Autodesk Fusion 360 part; units mm, degrees
(part 8 of 28)
sketch "Blinking Light House-F_Cu" plane through (0, 0, 1.4859) normal (0, 0, 1) x (1, 0, 0)
  line L0 (23.2295, 32.6644) -> (23.3427, 32.6091)
  line L1 (23.3427, 32.6091) -> (23.4319, 32.5199)
  line L2 (23.4319, 32.5199) -> (23.4872, 32.4067)
  line L3 (23.4872, 32.4067) -> (23.5031, 32.2975)
  line L4 (23.5031, 32.2975) -> (23.5031, 30.6131)
  line L5 (23.5031, 30.6131) -> (23.4872, 30.5039)
  line L6 (23.4872, 30.5039) -> (23.4319, 30.3907)
  line L7 (23.4319, 30.3907) -> (23.3427, 30.3016)
  line L8 (23.3427, 30.3016) -> (23.2295, 30.2462)
  line L9 (23.2295, 30.2462) -> (23.1203, 30.2303)
  line L10 (23.1203, 30.2303) -> (20.9864, 30.2303)
  line L11 (20.9864, 30.2303) -> (19.0583, 28.3022)
  line L12 (19.0583, 28.3022) -> (19.0583, 14.5419)
  line L13 (19.0583, 14.5419) -> (24.7601, 8.8401)
  line L14 (24.7601, 8.8401) -> (30.8402, 8.8401)
  line L15 (30.8402, 8.8401) -> (33.2244, 11.2242)
  line L16 (33.2244, 11.2242) -> (33.2244, 13.5949)
  line L17 (33.2244, 13.5949) -> (33.2295, 13.6733)
  line L18 (33.2295, 13.6733) -> (33.27, 13.8245)
  line L19 (33.27, 13.8245) -> (33.3483, 13.9602)
  line L20 (33.3483, 13.9602) -> (33.4001, 14.0192)
  line L21 (33.4001, 14.0192) -> (35.4955, 16.1146)
  line L22 (35.4955, 16.1146) -> (35.5545, 16.1663)
  line L23 (35.5545, 16.1663) -> (35.6901, 16.2446)
  line L24 (35.6901, 16.2446) -> (35.8414, 16.2852)
  line L25 (35.8414, 16.2852) -> (35.9197, 16.2903)
  line L26 (35.9197, 16.2903) -> (37.4913, 16.2903)
  line L27 (37.4913, 16.2903) -> (37.5696, 16.2852)
  line L28 (37.5696, 16.2852) -> (37.7209, 16.2446)
  line L29 (37.7209, 16.2446) -> (37.723, 16.2434)
  line L30 (37.723, 16.2434) -> (41.6943, 16.2434)
  line L31 (41.6943, 16.2434) -> (41.7173, 16.2778)
  line L32 (41.7173, 16.2778) -> (41.8559, 16.4164)
  line L33 (41.8559, 16.4164) -> (42.0189, 16.5253)
  line L34 (42.0189, 16.5253) -> (42.2, 16.6003)
  line L35 (42.2, 16.6003) -> (42.3923, 16.6386)
  line L36 (42.3923, 16.6386) -> (42.4903, 16.6434)
  line L37 (42.4903, 16.6434) -> (43.6903, 16.6434)
  line L38 (43.6903, 16.6434) -> (43.7883, 16.6386)
  line L39 (43.7883, 16.6386) -> (43.9806, 16.6003)
  line L40 (43.9806, 16.6003) -> (44.1617, 16.5253)
  line L41 (44.1617, 16.5253) -> (44.3247, 16.4164)
  line L42 (44.3247, 16.4164) -> (44.4633, 16.2778)
  line L43 (44.4633, 16.2778) -> (44.5722, 16.1148)
  line L44 (44.5722, 16.1148) -> (44.6472, 15.9337)
  line L45 (44.6472, 15.9337) -> (44.6855, 15.7414)
  line L46 (44.6855, 15.7414) -> (44.6855, 15.5454)
  line L47 (44.6855, 15.5454) -> (44.6472, 15.3531)
  line L48 (44.6472, 15.3531) -> (44.5722, 15.172)
  line L49 (44.5722, 15.172) -> (44.5073, 15.0749)
  line L50 (44.5073, 15.0749) -> (47.4649, 12.1173)
  line L51 (47.4649, 12.1173) -> (51.3447, 12.1173)
  line L52 (51.3447, 12.1173) -> (51.3717, 12.1704)
  line L53 (51.3717, 12.1704) -> (51.487, 12.3291)
  line L54 (51.487, 12.3291) -> (51.6257, 12.4678)
  line L55 (51.6257, 12.4678) -> (51.7844, 12.5831)
  line L56 (51.7844, 12.5831) -> (51.9592, 12.6722)
  line L57 (51.9592, 12.6722) -> (52.1457, 12.7328)
  line L58 (52.1457, 12.7328) -> (52.3395, 12.7635)
  line L59 (52.3395, 12.7635) -> (52.4375, 12.7673)
  line L60 (52.4375, 12.7673) -> (52.9375, 12.7673)
  line L61 (52.9375, 12.7673) -> (53.0356, 12.7635)
  line L62 (53.0356, 12.7635) -> (53.2293, 12.7328)
  line L63 (53.2293, 12.7328) -> (53.4159, 12.6722)
  line L64 (53.4159, 12.6722) -> (53.5907, 12.5831)
  line L65 (53.5907, 12.5831) -> (53.7493, 12.4678)
  line L66 (53.7493, 12.4678) -> (53.888, 12.3291)
  line L67 (53.888, 12.3291) -> (54.0033, 12.1704)
  line L68 (54.0033, 12.1704) -> (54.0924, 11.9957)
  line L69 (54.0924, 11.9957) -> (54.153, 11.8091)
  line L70 (54.153, 11.8091) -> (54.1837, 11.6154)
  line L71 (54.1837, 11.6154) -> (54.1837, 11.4192)
  line L72 (54.1837, 11.4192) -> (54.153, 11.2255)
  line L73 (54.153, 11.2255) -> (54.0924, 11.039)
  line L74 (54.0924, 11.039) -> (54.0033, 10.8642)
  line L75 (54.0033, 10.8642) -> (53.888, 10.7055)
  line L76 (53.888, 10.7055) -> (53.7493, 10.5668)
  line L77 (53.7493, 10.5668) -> (53.5907, 10.4515)
  line L78 (53.5907, 10.4515) -> (53.4159, 10.3625)
  line L79 (53.4159, 10.3625) -> (53.2293, 10.3018)
  line L80 (53.2293, 10.3018) -> (53.0356, 10.2712)
  line L81 (53.0356, 10.2712) -> (52.9375, 10.2673)
  line L82 (52.9375, 10.2673) -> (52.4375, 10.2673)
  line L83 (52.4375, 10.2673) -> (52.3395, 10.2712)
  line L84 (52.3395, 10.2712) -> (52.1457, 10.3018)
  line L85 (52.1457, 10.3018) -> (51.9592, 10.3625)
  line L86 (51.9592, 10.3625) -> (51.7844, 10.4515)
  line L87 (51.7844, 10.4515) -> (51.6257, 10.5668)
  line L88 (51.6257, 10.5668) -> (51.487, 10.7055)
  line L89 (51.487, 10.7055) -> (51.3717, 10.8642)
  line L90 (51.3717, 10.8642) -> (51.3447, 10.9173)
  line L91 (51.3447, 10.9173) -> (47.2164, 10.9173)
  line L92 (47.2164, 10.9173) -> (47.1381, 10.9224)
  line L93 (47.1381, 10.9224) -> (46.9868, 10.963)
  line L94 (46.9868, 10.963) -> (46.8552, 11.039)
  line L95 (46.8552, 11.039) -> (46.8511, 11.0413)
  line L96 (46.8511, 11.0413) -> (46.7921, 11.093)
  line L97 (46.7921, 11.093) -> (43.2418, 14.6434)
  line L98 (43.2418, 14.6434) -> (42.4903, 14.6434)
  line L99 (42.4903, 14.6434) -> (42.3923, 14.6482)
  line L100 (42.3923, 14.6482) -> (42.2, 14.6865)
  line L101 (42.2, 14.6865) -> (42.0189, 14.7615)
  line L102 (42.0189, 14.7615) -> (41.8559, 14.8704)
  line L103 (41.8559, 14.8704) -> (41.7173, 15.009)
  line L104 (41.7173, 15.009) -> (41.6943, 15.0434)
  line L105 (41.6943, 15.0434) -> (37.5382, 15.0434)
  line L106 (37.5382, 15.0434) -> (37.4598, 15.0485)
  line L107 (37.4598, 15.0485) -> (37.3086, 15.0891)
  line L108 (37.3086, 15.0891) -> (37.3064, 15.0903)
  line L109 (37.3064, 15.0903) -> (36.1683, 15.0903)
  line L110 (36.1683, 15.0903) -> (34.4244, 13.3464)
  line L111 (34.4244, 13.3464) -> (34.4244, 10.9757)
  line L112 (34.4244, 10.9757) -> (34.4192, 10.8974)
  line L113 (34.4192, 10.8974) -> (34.3787, 10.7461)
  line L114 (34.3787, 10.7461) -> (34.3004, 10.6105)
  line L115 (34.3004, 10.6105) -> (34.2486, 10.5515)
  line L116 (34.2486, 10.5515) -> (31.513, 7.8158)
  line L117 (31.513, 7.8158) -> (31.454, 7.7641)
  line L118 (31.454, 7.7641) -> (31.3183, 7.6858)
  line L119 (31.3183, 7.6858) -> (31.1671, 7.6452)
  line L120 (31.1671, 7.6452) -> (31.0887, 7.6401)
  line L121 (31.0887, 7.6401) -> (24.5116, 7.6401)
  line L122 (24.5116, 7.6401) -> (24.4333, 7.6452)
  line L123 (24.4333, 7.6452) -> (24.282, 7.6858)
  line L124 (24.282, 7.6858) -> (24.1463, 7.7641)
  line L125 (24.1463, 7.7641) -> (24.0873, 7.8158)
  line L126 (24.0873, 7.8158) -> (18.034, 13.8691)
  line L127 (18.034, 13.8691) -> (17.9823, 13.9281)
  line L128 (17.9823, 13.9281) -> (17.904, 14.0638)
  line L129 (17.904, 14.0638) -> (17.8634, 14.2151)
  line L130 (17.8634, 14.2151) -> (17.8583, 14.2934)
  line L131 (17.8583, 14.2934) -> (17.8583, 28.5507)
  line L132 (17.8583, 28.5507) -> (17.8634, 28.629)
  line L133 (17.8634, 28.629) -> (17.904, 28.7803)
  line L134 (17.904, 28.7803) -> (17.9823, 28.916)
  line L135 (17.9823, 28.916) -> (18.034, 28.975)
  line L136 (18.034, 28.975) -> (20.5031, 31.444)
  line L137 (20.5031, 31.444) -> (20.5031, 32.2975)
  line L138 (20.5031, 32.2975) -> (20.519, 32.4067)
  line L139 (20.519, 32.4067) -> (20.5744, 32.5199)
  line L140 (20.5744, 32.5199) -> (20.6635, 32.6091)
  line L141 (20.6635, 32.6091) -> (20.7767, 32.6644)
  line L142 (20.7767, 32.6644) -> (20.8859, 32.6803)
  line L143 (20.8859, 32.6803) -> (23.1203, 32.6803)
  line L144 (23.1203, 32.6803) -> (23.2295, 32.6644)
  line L145 (84.1895, 32.6644) -> (84.3027, 32.6091)
  line L146 (84.3027, 32.6091) -> (84.3919, 32.5199)
  line L147 (84.3919, 32.5199) -> (84.4472, 32.4067)
  line L148 (84.4472, 32.4067) -> (84.4631, 32.2975)
  line L149 (84.4631, 32.2975) -> (84.4631, 30.6131)
  line L150 (84.4631, 30.6131) -> (84.4472, 30.5039)
  line L151 (84.4472, 30.5039) -> (84.3919, 30.3907)
  line L152 (84.3919, 30.3907) -> (84.3027, 30.3016)
  line L153 (84.3027, 30.3016) -> (84.1895, 30.2462)
  line L154 (84.1895, 30.2462) -> (84.0803, 30.2303)
  line L155 (84.0803, 30.2303) -> (81.9464, 30.2303)
  line L156 (81.9464, 30.2303) -> (80.0183, 28.3022)
  line L157 (80.0183, 28.3022) -> (80.0183, 14.5419)
  line L158 (80.0183, 14.5419) -> (85.7201, 8.8401)
  line L159 (85.7201, 8.8401) -> (91.8002, 8.8401)
  line L160 (91.8002, 8.8401) -> (94.1844, 11.2242)
  line L161 (94.1844, 11.2242) -> (94.1844, 13.5949)
  line L162 (94.1844, 13.5949) -> (94.1895, 13.6733)
  line L163 (94.1895, 13.6733) -> (94.23, 13.8245)
  line L164 (94.23, 13.8245) -> (94.3083, 13.9602)
  line L165 (94.3084, 13.9602) -> (94.3601, 14.0192)
  line L166 (94.3601, 14.0192) -> (96.4555, 16.1146)
  line L167 (96.4555, 16.1146) -> (96.5145, 16.1663)
  line L168 (96.5145, 16.1663) -> (96.6501, 16.2446)
  line L169 (96.6501, 16.2446) -> (96.8014, 16.2852)
  line L170 (96.8014, 16.2852) -> (96.8797, 16.2903)
  line L171 (96.8797, 16.2903) -> (98.4513, 16.2903)
  line L172 (98.4513, 16.2903) -> (98.5296, 16.2852)
  line L173 (98.5296, 16.2852) -> (98.6809, 16.2446)
  line L174 (98.6809, 16.2446) -> (98.683, 16.2434)
  line L175 (98.683, 16.2434) -> (102.6543, 16.2434)
  line L176 (102.6543, 16.2434) -> (102.6773, 16.2778)
  line L177 (102.6773, 16.2778) -> (102.8159, 16.4164)
  line L178 (102.8159, 16.4164) -> (102.9789, 16.5253)
  line L179 (102.9789, 16.5253) -> (103.16, 16.6003)
  line L180 (103.16, 16.6003) -> (103.3523, 16.6386)
  line L181 (103.3523, 16.6386) -> (103.4503, 16.6434)
  line L182 (103.4503, 16.6434) -> (104.6503, 16.6434)
  line L183 (104.6503, 16.6434) -> (104.7483, 16.6386)
  line L184 (104.7483, 16.6386) -> (104.9406, 16.6003)
  line L185 (104.9406, 16.6003) -> (105.1217, 16.5253)
  line L186 (105.1217, 16.5253) -> (105.2847, 16.4164)
  line L187 (105.2847, 16.4164) -> (105.4233, 16.2778)
  line L188 (105.4233, 16.2778) -> (105.5322, 16.1148)
  line L189 (105.5322, 16.1148) -> (105.6072, 15.9337)
  line L190 (105.6072, 15.9337) -> (105.6455, 15.7414)
  line L191 (105.6455, 15.7414) -> (105.6455, 15.5454)
  line L192 (105.6455, 15.5454) -> (105.6072, 15.3531)
  line L193 (105.6072, 15.3531) -> (105.5322, 15.172)
  line L194 (105.5322, 15.172) -> (105.4673, 15.0749)
  line L195 (105.4673, 15.0749) -> (108.4249, 12.1173)
  line L196 (108.4249, 12.1173) -> (112.3047, 12.1173)
  line L197 (112.3047, 12.1173) -> (112.3317, 12.1704)
  line L198 (112.3317, 12.1704) -> (112.447, 12.3291)
  line L199 (112.447, 12.3291) -> (112.5857, 12.4678)
  line L200 (112.5857, 12.4678) -> (112.7444, 12.5831)
  line L201 (112.7444, 12.5831) -> (112.9192, 12.6722)
  line L202 (112.9192, 12.6722) -> (113.1057, 12.7328)
  line L203 (113.1057, 12.7328) -> (113.2995, 12.7635)
  line L204 (113.2995, 12.7635) -> (113.3975, 12.7673)
  line L205 (113.3975, 12.7673) -> (113.8975, 12.7673)
  line L206 (113.8975, 12.7673) -> (113.9956, 12.7635)
  line L207 (113.9956, 12.7635) -> (114.1893, 12.7328)
  line L208 (114.1893, 12.7328) -> (114.3759, 12.6722)
  line L209 (114.3759, 12.6722) -> (114.5507, 12.5831)
  line L210 (114.5507, 12.5831) -> (114.7093, 12.4678)
  line L211 (114.7093, 12.4678) -> (114.848, 12.3291)
  line L212 (114.848, 12.3291) -> (114.9633, 12.1704)
  line L213 (114.9633, 12.1704) -> (115.0524, 11.9957)
  line L214 (115.0524, 11.9957) -> (115.113, 11.8091)
  line L215 (115.113, 11.8091) -> (115.1437, 11.6154)
  line L216 (115.1437, 11.6154) -> (115.1437, 11.4192)
  line L217 (115.1437, 11.4192) -> (115.113, 11.2255)
  line L218 (115.113, 11.2255) -> (115.0524, 11.039)
  line L219 (115.0524, 11.039) -> (114.9633, 10.8642)
  line L220 (114.9633, 10.8642) -> (114.848, 10.7055)
  line L221 (114.848, 10.7055) -> (114.7093, 10.5668)
  line L222 (114.7093, 10.5668) -> (114.5507, 10.4515)
  line L223 (114.5507, 10.4515) -> (114.3759, 10.3625)
  line L224 (114.3759, 10.3625) -> (114.1893, 10.3018)
  line L225 (114.1893, 10.3018) -> (113.9956, 10.2712)
  line L226 (113.9956, 10.2712) -> (113.8975, 10.2673)
  line L227 (113.8975, 10.2673) -> (113.3975, 10.2673)
  line L228 (113.3975, 10.2673) -> (113.2995, 10.2712)
  line L229 (113.2995, 10.2712) -> (113.1057, 10.3018)
  line L230 (113.1057, 10.3018) -> (112.9192, 10.3625)
  line L231 (112.9192, 10.3625) -> (112.7444, 10.4515)
  line L232 (112.7444, 10.4515) -> (112.5857, 10.5668)
  line L233 (112.5857, 10.5668) -> (112.447, 10.7055)
  line L234 (112.447, 10.7055) -> (112.3317, 10.8642)
  line L235 (112.3317, 10.8642) -> (112.3047, 10.9173)
  line L236 (112.3047, 10.9173) -> (108.1764, 10.9173)
  line L237 (108.1764, 10.9173) -> (108.0981, 10.9224)
  line L238 (108.0981, 10.9224) -> (107.9468, 10.963)
  line L239 (107.9468, 10.963) -> (107.8152, 11.039)
  line L240 (107.8152, 11.039) -> (107.8111, 11.0413)
  line L241 (107.8111, 11.0413) -> (107.7521, 11.093)
  line L242 (107.7521, 11.093) -> (104.2018, 14.6434)
  line L243 (104.2018, 14.6434) -> (103.4503, 14.6434)
  line L244 (103.4503, 14.6434) -> (103.3523, 14.6482)
  line L245 (103.3523, 14.6482) -> (103.16, 14.6865)
  line L246 (103.16, 14.6865) -> (102.9789, 14.7615)
  line L247 (102.9789, 14.7615) -> (102.8159, 14.8704)
  line L248 (102.8159, 14.8704) -> (102.6773, 15.009)
  line L249 (102.6773, 15.009) -> (102.6543, 15.0434)
  line L250 (102.6543, 15.0434) -> (98.4982, 15.0434)
  line L251 (98.4982, 15.0434) -> (98.4198, 15.0485)
  line L252 (98.4198, 15.0485) -> (98.2686, 15.0891)
  line L253 (98.2686, 15.0891) -> (98.2664, 15.0903)
  line L254 (98.2664, 15.0903) -> (97.1283, 15.0903)
  line L255 (97.1283, 15.0903) -> (95.3844, 13.3464)
  line L256 (95.3844, 13.3464) -> (95.3844, 10.9757)
  line L257 (95.3844, 10.9757) -> (95.3792, 10.8974)
  line L258 (95.3792, 10.8974) -> (95.3387, 10.7461)
  line L259 (95.3387, 10.7461) -> (95.2604, 10.6105)
  line L260 (95.2604, 10.6105) -> (95.2086, 10.5515)
  line L261 (95.2086, 10.5515) -> (92.473, 7.8158)
  line L262 (92.473, 7.8158) -> (92.414, 7.7641)
  line L263 (92.414, 7.7641) -> (92.2783, 7.6858)
  line L264 (92.2783, 7.6858) -> (92.1271, 7.6452)
  line L265 (92.1271, 7.6452) -> (92.0487, 7.6401)
  line L266 (92.0487, 7.6401) -> (85.4716, 7.6401)
  line L267 (85.4716, 7.6401) -> (85.3933, 7.6452)
  line L268 (85.3933, 7.6452) -> (85.242, 7.6858)
  line L269 (85.242, 7.6858) -> (85.1063, 7.7641)
  line L270 (85.1063, 7.7641) -> (85.0473, 7.8158)
  line L271 (85.0473, 7.8158) -> (78.994, 13.8691)
  line L272 (78.994, 13.8691) -> (78.9423, 13.9281)
  line L273 (78.9423, 13.9281) -> (78.864, 14.0638)
  line L274 (78.864, 14.0638) -> (78.8234, 14.2151)
  line L275 (78.8234, 14.2151) -> (78.8183, 14.2934)
  line L276 (78.8183, 14.2934) -> (78.8183, 28.5507)
  line L277 (78.8183, 28.5507) -> (78.8234, 28.629)
  line L278 (78.8234, 28.629) -> (78.864, 28.7803)
  line L279 (78.864, 28.7803) -> (78.9423, 28.916)
  line L280 (78.9423, 28.916) -> (78.994, 28.975)
  line L281 (78.994, 28.975) -> (81.4631, 31.444)
  line L282 (81.4631, 31.444) -> (81.4631, 32.2975)
  line L283 (81.4631, 32.2975) -> (81.479, 32.4067)
  line L284 (81.479, 32.4067) -> (81.5344, 32.5199)
  line L285 (81.5344, 32.5199) -> (81.6235, 32.6091)
  line L286 (81.6235, 32.6091) -> (81.7367, 32.6644)
  line L287 (81.7367, 32.6644) -> (81.8459, 32.6803)
  line L288 (81.8459, 32.6803) -> (84.0803, 32.6803)
  line L289 (84.0803, 32.6803) -> (84.1895, 32.6644)
  line L290 (50.1338, 24.7863) -> (50.3204, 24.7257)
  line L291 (50.3204, 24.7257) -> (50.4952, 24.6366)
  line L292 (50.4952, 24.6366) -> (50.6538, 24.5213)
  line L293 (50.6538, 24.5213) -> (50.7925, 24.3826)
  line L294 (50.7925, 24.3826) -> (50.9078, 24.2239)
  line L295 (50.9078, 24.2239) -> (50.9969, 24.0492)
  line L296 (50.9969, 24.0492) -> (51.0575, 23.8626)
  line L297 (51.0575, 23.8626) -> (51.0882, 23.6689)
  line L298 (51.0882, 23.6689) -> (51.092, 23.5708)
  line L299 (51.092, 23.5708) -> (51.092, 23.0708)
  line L300 (51.092, 23.0708) -> (51.0882, 22.9727)
  line L301 (51.0882, 22.9727) -> (51.0814, 22.93)
  line L302 (51.0814, 22.93) -> (60.7318, 13.2796)
  line L303 (60.7318, 13.2796) -> (60.7835, 13.2206)
  line L304 (60.7835, 13.2206) -> (60.8619, 13.0849)
  line L305 (60.8619, 13.0849) -> (60.9024, 12.9336)
  line L306 (60.9024, 12.9336) -> (60.9075, 12.8553)
  line L307 (60.9075, 12.8553) -> (60.9075, 12.7139)
  line L308 (60.9075, 12.7139) -> (61.0359, 12.6722)
  line L309 (61.0359, 12.6722) -> (61.2107, 12.5831)
  line L310 (61.2107, 12.5831) -> (61.3693, 12.4678)
  line L311 (61.3693, 12.4678) -> (61.508, 12.3291)
  line L312 (61.508, 12.3291) -> (61.6233, 12.1704)
  line L313 (61.6233, 12.1704) -> (61.7124, 11.9957)
  line L314 (61.7124, 11.9957) -> (61.773, 11.8091)
  line L315 (61.773, 11.8091) -> (61.8037, 11.6154)
  line L316 (61.8037, 11.6154) -> (61.8037, 11.4192)
  line L317 (61.8037, 11.4192) -> (61.773, 11.2255)
  line L318 (61.773, 11.2255) -> (61.7124, 11.039)
  line L319 (61.7124, 11.039) -> (61.6233, 10.8642)
  line L320 (61.6233, 10.8642) -> (61.508, 10.7055)
  line L321 (61.508, 10.7055) -> (61.3693, 10.5668)
  line L322 (61.3693, 10.5668) -> (61.2107, 10.4515)
  line L323 (61.2107, 10.4515) -> (61.0359, 10.3625)
  line L324 (61.0359, 10.3625) -> (60.8493, 10.3018)
  line L325 (60.8493, 10.3018) -> (60.6556, 10.2712)
  line L326 (60.6556, 10.2712) -> (60.5575, 10.2673)
  line L327 (60.5575, 10.2673) -> (60.0575, 10.2673)
  line L328 (60.0575, 10.2673) -> (59.9595, 10.2712)
  line L329 (59.9595, 10.2712) -> (59.9167, 10.2779)
  line L330 (59.9167, 10.2779) -> (57.47, 7.8312)
  line L331 (57.47, 7.8312) -> (57.411, 7.7795)
  line L332 (57.411, 7.7795) -> (57.2753, 7.7012)
  line L333 (57.2753, 7.7012) -> (57.1241, 7.6606)
  line L334 (57.1241, 7.6606) -> (57.0457, 7.6555)
  line L335 (57.0457, 7.6555) -> (41.0732, 7.6555)
  line L336 (41.0732, 7.6555) -> (40.9949, 7.6606)
  line L337 (40.9949, 7.6606) -> (40.8436, 7.7012)
  line L338 (40.8436, 7.7012) -> (40.7079, 7.7795)
  line L339 (40.7079, 7.7795) -> (40.6489, 7.8312)
  line L340 (40.6489, 7.8312) -> (37.3526, 11.1276)
  line L341 (37.3526, 11.1276) -> (37.3098, 11.1208)
  line L342 (37.3098, 11.1208) -> (37.2117, 11.117)
  line L343 (37.2117, 11.117) -> (36.7117, 11.117)
  line L344 (36.7117, 11.117) -> (36.6137, 11.1208)
  line L345 (36.6137, 11.1208) -> (36.4199, 11.1515)
  line L346 (36.4199, 11.1515) -> (36.2334, 11.2121)
  line L347 (36.2334, 11.2121) -> (36.0586, 11.3012)
  line L348 (36.0586, 11.3012) -> (35.8999, 11.4165)
  line L349 (35.8999, 11.4165) -> (35.7612, 11.5551)
  line L350 (35.7612, 11.5551) -> (35.6459, 11.7138)
  line L351 (35.6459, 11.7138) -> (35.5569, 11.8886)
  line L352 (35.5569, 11.8886) -> (35.4963, 12.0751)
  line L353 (35.4963, 12.0751) -> (35.4656, 12.2689)
  line L354 (35.4656, 12.2689) -> (35.4656, 12.465)
  line L355 (35.4656, 12.465) -> (35.4963, 12.6588)
  line L356 (35.4963, 12.6588) -> (35.5569, 12.8453)
  line L357 (35.5569, 12.8453) -> (35.6459, 13.0201)
  line L358 (35.6459, 13.0201) -> (35.7612, 13.1788)
  line L359 (35.7612, 13.1788) -> (35.8999, 13.3175)
  line L360 (35.8999, 13.3175) -> (36.0586, 13.4328)
  line L361 (36.0586, 13.4328) -> (36.2334, 13.5218)
  line L362 (36.2334, 13.5218) -> (36.4199, 13.5824)
  line L363 (36.4199, 13.5824) -> (36.6137, 13.6131)
  line L364 (36.6137, 13.6131) -> (36.7117, 13.617)
  line L365 (36.7117, 13.617) -> (37.2117, 13.617)
  line L366 (37.2117, 13.617) -> (37.3098, 13.6131)
  line L367 (37.3098, 13.6131) -> (37.5035, 13.5824)
  line L368 (37.5035, 13.5824) -> (37.6901, 13.5218)
  line L369 (37.6901, 13.5218) -> (37.8649, 13.4328)
  line L370 (37.8649, 13.4328) -> (38.0236, 13.3175)
  line L371 (38.0236, 13.3175) -> (38.1622, 13.1788)
  line L372 (38.1622, 13.1788) -> (38.2775, 13.0201)
  line L373 (38.2775, 13.0201) -> (38.3666, 12.8453)
  line L374 (38.3666, 12.8453) -> (38.4272, 12.6588)
  line L375 (38.4272, 12.6588) -> (38.4579, 12.465)
  line L376 (38.4579, 12.465) -> (38.4579, 12.2689)
  line L377 (38.4579, 12.2689) -> (38.4272, 12.0752)
  line L378 (38.4272, 12.0752) -> (38.3666, 11.8886)
  line L379 (38.3666, 11.8886) -> (38.3403, 11.837)
  line L380 (38.3403, 11.837) -> (41.3217, 8.8555)
  line L381 (41.3217, 8.8555) -> (56.7972, 8.8555)
  line L382 (56.7972, 8.8555) -> (58.929, 10.9873)
  line L383 (58.929, 10.9873) -> (58.9027, 11.039)
  line L384 (58.9027, 11.039) -> (58.8421, 11.2255)
  line L385 (58.8421, 11.2255) -> (58.8114, 11.4192)
  line L386 (58.8114, 11.4192) -> (58.8114, 11.6154)
  line L387 (58.8114, 11.6154) -> (58.8421, 11.8091)
  line L388 (58.8421, 11.8091) -> (58.9027, 11.9957)
  line L389 (58.9027, 11.9957) -> (58.9917, 12.1704)
  line L390 (58.9917, 12.1704) -> (59.107, 12.3291)
  line L391 (59.107, 12.3291) -> (59.2457, 12.4678)
  line L392 (59.2457, 12.4678) -> (59.4044, 12.5831)
  line L393 (59.4044, 12.5831) -> (59.5792, 12.6722)
  line L394 (59.5792, 12.6722) -> (59.6267, 12.6876)
  line L395 (59.6267, 12.6876) -> (50.372, 21.9423)
  line L396 (50.372, 21.9423) -> (50.3204, 21.916)
  line L397 (50.3204, 21.916) -> (50.1338, 21.8554)
  line L398 (50.1338, 21.8554) -> (49.9401, 21.8247)
  line L399 (49.9401, 21.8247) -> (49.744, 21.8247)
  line L400 (49.744, 21.8247) -> (49.5502, 21.8554)
  line L401 (49.5502, 21.8554) -> (49.3637, 21.916)
  line L402 (49.3637, 21.916) -> (49.1889, 22.005)
  line L403 (49.1889, 22.005) -> (49.0302, 22.1203)
  line L404 (49.0302, 22.1203) -> (48.8915, 22.259)
  line L405 (48.8915, 22.259) -> (48.7762, 22.4177)
  line L406 (48.7762, 22.4177) -> (48.6872, 22.5925)
  line L407 (48.6872, 22.5925) -> (48.6266, 22.779)
  line L408 (48.6266, 22.779) -> (48.5959, 22.9727)
  line L409 (48.5959, 22.9727) -> (48.592, 23.0708)
  line L410 (48.592, 23.0708) -> (48.592, 23.5708)
  line L411 (48.592, 23.5708) -> (48.5959, 23.6689)
  line L412 (48.5959, 23.6689) -> (48.6266, 23.8626)
  line L413 (48.6266, 23.8626) -> (48.6872, 24.0492)
  line L414 (48.6872, 24.0492) -> (48.7762, 24.2239)
  line L415 (48.7762, 24.2239) -> (48.8915, 24.3826)
  line L416 (48.8915, 24.3826) -> (49.0302, 24.5213)
  line L417 (49.0302, 24.5213) -> (49.1889, 24.6366)
  line L418 (49.1889, 24.6366) -> (49.3637, 24.7257)
  line L419 (49.3637, 24.7257) -> (49.5502, 24.7863)
  line L420 (49.5502, 24.7863) -> (49.744, 24.817)
  line L421 (49.744, 24.817) -> (49.9401, 24.817)
  line L422 (49.9401, 24.817) -> (50.1338, 24.7863)
  line L423 (111.0938, 24.7863) -> (111.2804, 24.7257)
  line L424 (111.2804, 24.7257) -> (111.4552, 24.6366)
  line L425 (111.4552, 24.6366) -> (111.6138, 24.5213)
  line L426 (111.6138, 24.5213) -> (111.7525, 24.3826)
  line L427 (111.7525, 24.3826) -> (111.8678, 24.2239)
  line L428 (111.8678, 24.2239) -> (111.9569, 24.0492)
  line L429 (111.9569, 24.0492) -> (112.0175, 23.8626)
  line L430 (112.0175, 23.8626) -> (112.0482, 23.6689)
  line L431 (112.0482, 23.6689) -> (112.052, 23.5708)
  line L432 (112.052, 23.5708) -> (112.052, 23.0708)
  line L433 (112.052, 23.0708) -> (112.0482, 22.9727)
  line L434 (112.0482, 22.9727) -> (112.0414, 22.93)
  line L435 (112.0414, 22.93) -> (121.6918, 13.2796)
  line L436 (121.6918, 13.2796) -> (121.7435, 13.2206)
  line L437 (121.7435, 13.2206) -> (121.8219, 13.0849)
  line L438 (121.8219, 13.0849) -> (121.8624, 12.9336)
  line L439 (121.8624, 12.9336) -> (121.8675, 12.8553)
  line L440 (121.8675, 12.8553) -> (121.8675, 12.7139)
  line L441 (121.8675, 12.7139) -> (121.9959, 12.6722)
  line L442 (121.9959, 12.6722) -> (122.1707, 12.5831)
  line L443 (122.1707, 12.5831) -> (122.3293, 12.4678)
  line L444 (122.3293, 12.4678) -> (122.468, 12.3291)
  line L445 (122.468, 12.3291) -> (122.5833, 12.1704)
  line L446 (122.5833, 12.1704) -> (122.6724, 11.9957)
  line L447 (122.6724, 11.9957) -> (122.733, 11.8091)
  line L448 (122.733, 11.8091) -> (122.7637, 11.6154)
  line L449 (122.7637, 11.6154) -> (122.7637, 11.4192)
  line L450 (122.7637, 11.4192) -> (122.733, 11.2255)
  line L451 (122.733, 11.2255) -> (122.6724, 11.039)
  line L452 (122.6724, 11.039) -> (122.5833, 10.8642)
  line L453 (122.5833, 10.8642) -> (122.468, 10.7055)
  line L454 (122.468, 10.7055) -> (122.3293, 10.5668)
  line L455 (122.3293, 10.5668) -> (122.1707, 10.4515)
  line L456 (122.1707, 10.4515) -> (121.9959, 10.3625)
  line L457 (121.9959, 10.3625) -> (121.8093, 10.3018)
  line L458 (121.8093, 10.3018) -> (121.6156, 10.2712)
  line L459 (121.6156, 10.2712) -> (121.5175, 10.2673)
  line L460 (121.5175, 10.2673) -> (121.0175, 10.2673)
  line L461 (121.0175, 10.2673) -> (120.9195, 10.2712)
  line L462 (120.9195, 10.2712) -> (120.8767, 10.2779)
  line L463 (120.8767, 10.2779) -> (118.43, 7.8312)
  line L464 (118.43, 7.8312) -> (118.371, 7.7795)
  line L465 (118.371, 7.7795) -> (118.2353, 7.7012)
  line L466 (118.2353, 7.7012) -> (118.0841, 7.6606)
  line L467 (118.0841, 7.6606) -> (118.0057, 7.6555)
  line L468 (118.0057, 7.6555) -> (102.0332, 7.6555)
  line L469 (102.0332, 7.6555) -> (101.9549, 7.6606)
  line L470 (101.9549, 7.6606) -> (101.8036, 7.7012)
  line L471 (101.8036, 7.7012) -> (101.6679, 7.7795)
  line L472 (101.6679, 7.7795) -> (101.6089, 7.8312)
  line L473 (101.6089, 7.8312) -> (98.3126, 11.1276)
  line L474 (98.3126, 11.1276) -> (98.2698, 11.1208)
  line L475 (98.2698, 11.1208) -> (98.1717, 11.117)
  line L476 (98.1717, 11.117) -> (97.6717, 11.117)
  line L477 (97.6717, 11.117) -> (97.5737, 11.1208)
  line L478 (97.5737, 11.1208) -> (97.3799, 11.1515)
  line L479 (97.3799, 11.1515) -> (97.1934, 11.2121)
  line L480 (97.1934, 11.2121) -> (97.0186, 11.3012)
  line L481 (97.0186, 11.3012) -> (96.8599, 11.4165)
  line L482 (96.8599, 11.4165) -> (96.7212, 11.5551)
  line L483 (96.7212, 11.5551) -> (96.6059, 11.7138)
  line L484 (96.6059, 11.7138) -> (96.5169, 11.8886)
  line L485 (96.5169, 11.8886) -> (96.4563, 12.0751)
  line L486 (96.4563, 12.0751) -> (96.4256, 12.2689)
  line L487 (96.4256, 12.2689) -> (96.4256, 12.465)
  line L488 (96.4256, 12.465) -> (96.4563, 12.6588)
  line L489 (96.4563, 12.6588) -> (96.5169, 12.8453)
  line L490 (96.5169, 12.8453) -> (96.6059, 13.0201)
  line L491 (96.6059, 13.0201) -> (96.7212, 13.1788)
  line L492 (96.7212, 13.1788) -> (96.8599, 13.3175)
  line L493 (96.8599, 13.3175) -> (97.0186, 13.4328)
  line L494 (97.0186, 13.4328) -> (97.1934, 13.5218)
  line L495 (97.1934, 13.5218) -> (97.3799, 13.5824)
  line L496 (97.3799, 13.5824) -> (97.5737, 13.6131)
  line L497 (97.5737, 13.6131) -> (97.6717, 13.617)
  line L498 (97.6717, 13.617) -> (98.1717, 13.617)
  line L499 (98.1717, 13.617) -> (98.2698, 13.6131)
  line L500 (98.2698, 13.6131) -> (98.4635, 13.5824)
  line L501 (98.4635, 13.5824) -> (98.6501, 13.5218)
  line L502 (98.6501, 13.5218) -> (98.8249, 13.4328)
  line L503 (98.8249, 13.4328) -> (98.9836, 13.3175)
  line L504 (98.9836, 13.3175) -> (99.1222, 13.1788)
  line L505 (99.1222, 13.1788) -> (99.2375, 13.0201)
  line L506 (99.2375, 13.0201) -> (99.3266, 12.8453)
  line L507 (99.3266, 12.8453) -> (99.3872, 12.6588)
  line L508 (99.3872, 12.6588) -> (99.4179, 12.465)
  line L509 (99.4179, 12.465) -> (99.4179, 12.2689)
  line L510 (99.4179, 12.2689) -> (99.3872, 12.0752)
  line L511 (99.3872, 12.0752) -> (99.3266, 11.8886)
  line L512 (99.3266, 11.8886) -> (99.3003, 11.837)
  line L513 (99.3003, 11.837) -> (102.2817, 8.8555)
  line L514 (102.2817, 8.8555) -> (117.7572, 8.8555)
  line L515 (117.7572, 8.8555) -> (119.889, 10.9873)
  line L516 (119.889, 10.9873) -> (119.8627, 11.039)
  line L517 (119.8627, 11.039) -> (119.8021, 11.2255)
  line L518 (119.8021, 11.2255) -> (119.7714, 11.4192)
  line L519 (119.7714, 11.4192) -> (119.7714, 11.6154)
  line L520 (119.7714, 11.6154) -> (119.8021, 11.8091)
  line L521 (119.8021, 11.8091) -> (119.8627, 11.9957)
  line L522 (119.8627, 11.9957) -> (119.9517, 12.1704)
  line L523 (119.9517, 12.1704) -> (120.067, 12.3291)
  line L524 (120.067, 12.3291) -> (120.2057, 12.4678)
  line L525 (120.2057, 12.4678) -> (120.3644, 12.5831)
  line L526 (120.3644, 12.5831) -> (120.5392, 12.6722)
  line L527 (120.5392, 12.6722) -> (120.5867, 12.6876)
  line L528 (120.5867, 12.6876) -> (111.332, 21.9423)
  line L529 (111.332, 21.9423) -> (111.2804, 21.916)
  line L530 (111.2804, 21.916) -> (111.0938, 21.8554)
  line L531 (111.0938, 21.8554) -> (110.9001, 21.8247)
  line L532 (110.9001, 21.8247) -> (110.704, 21.8247)
  line L533 (110.704, 21.8247) -> (110.5102, 21.8554)
  line L534 (110.5102, 21.8554) -> (110.3237, 21.916)
  line L535 (110.3237, 21.916) -> (110.1489, 22.005)
  line L536 (110.1489, 22.005) -> (109.9902, 22.1203)
  line L537 (109.9902, 22.1203) -> (109.8515, 22.259)
  line L538 (109.8515, 22.259) -> (109.7362, 22.4177)
  line L539 (109.7362, 22.4177) -> (109.6472, 22.5925)
  line L540 (109.6472, 22.5925) -> (109.5866, 22.779)
  line L541 (109.5866, 22.779) -> (109.5559, 22.9727)
  line L542 (109.5559, 22.9727) -> (109.552, 23.0708)
  line L543 (109.552, 23.0708) -> (109.552, 23.5708)
  line L544 (109.552, 23.5708) -> (109.5559, 23.6689)
  line L545 (109.5559, 23.6689) -> (109.5866, 23.8626)
  line L546 (109.5866, 23.8626) -> (109.6472, 24.0492)
  line L547 (109.6472, 24.0492) -> (109.7362, 24.2239)
  line L548 (109.7362, 24.2239) -> (109.8515, 24.3826)
  line L549 (109.8515, 24.3826) -> (109.9902, 24.5213)
  line L550 (109.9902, 24.5213) -> (110.1489, 24.6366)
  line L551 (110.1489, 24.6366) -> (110.3237, 24.7257)
  line L552 (110.3237, 24.7257) -> (110.5102, 24.7863)
  line L553 (110.5102, 24.7863) -> (110.704, 24.817)
  line L554 (110.704, 24.817) -> (110.9001, 24.817)
  line L555 (110.9001, 24.817) -> (111.0938, 24.7863)
  line L556 (43.7883, 19.3686) -> (43.9806, 19.3303)
  line L557 (43.9806, 19.3303) -> (44.1617, 19.2553)
  line L558 (44.1617, 19.2553) -> (44.3247, 19.1464)
  line L559 (44.3247, 19.1464) -> (44.4633, 19.0078)
  line L560 (44.4633, 19.0078) -> (44.5722, 18.8448)
  line L561 (44.5722, 18.8448) -> (44.6472, 18.6637)
  line L562 (44.6472, 18.6637) -> (44.6855, 18.4714)
  line L563 (44.6855, 18.4714) -> (44.6855, 18.2754)
  line L564 (44.6855, 18.2754) -> (44.6472, 18.0831)
  line L565 (44.6472, 18.0831) -> (44.5722, 17.902)
  line L566 (44.5722, 17.902) -> (44.4633, 17.739)
  line L567 (44.4633, 17.739) -> (44.3247, 17.6004)
  line L568 (44.3247, 17.6004) -> (44.1617, 17.4915)
  line L569 (44.1617, 17.4915) -> (43.9806, 17.4165)
  line L570 (43.9806, 17.4165) -> (43.7883, 17.3782)
  line L571 (43.7883, 17.3782) -> (43.6903, 17.3734)
  line L572 (43.6903, 17.3734) -> (42.4903, 17.3734)
  line L573 (42.4903, 17.3734) -> (42.3923, 17.3782)
  line L574 (42.3923, 17.3782) -> (42.2, 17.4165)
  line L575 (42.2, 17.4165) -> (42.0189, 17.4915)
  line L576 (42.0189, 17.4915) -> (41.8559, 17.6004)
  line L577 (41.8559, 17.6004) -> (41.7173, 17.739)
  line L578 (41.7173, 17.739) -> (41.6943, 17.7734)
  line L579 (41.6943, 17.7734) -> (35.5967, 17.7734)
  line L580 (35.5967, 17.7734) -> (30.7203, 12.897)
  line L581 (30.7203, 12.897) -> (30.7466, 12.8453)
  line L582 (30.7466, 12.8453) -> (30.8072, 12.6588)
  line L583 (30.8072, 12.6588) -> (30.8379, 12.465)
  line L584 (30.8379, 12.465) -> (30.8379, 12.2689)
  line L585 (30.8379, 12.2689) -> (30.8072, 12.0752)
  line L586 (30.8072, 12.0752) -> (30.7466, 11.8886)
  line L587 (30.7466, 11.8886) -> (30.6575, 11.7138)
  line L588 (30.6575, 11.7138) -> (30.5422, 11.5551)
  line L589 (30.5422, 11.5551) -> (30.4036, 11.4165)
  line L590 (30.4036, 11.4165) -> (30.2449, 11.3012)
  line L591 (30.2449, 11.3012) -> (30.0701, 11.2121)
  line L592 (30.0701, 11.2121) -> (29.8835, 11.1515)
  line L593 (29.8835, 11.1515) -> (29.6898, 11.1208)
  line L594 (29.6898, 11.1208) -> (29.5917, 11.117)
  line L595 (29.5917, 11.117) -> (29.0917, 11.117)
  line L596 (29.0917, 11.117) -> (28.9937, 11.1208)
  line L597 (28.9937, 11.1208) -> (28.7999, 11.1515)
  line L598 (28.7999, 11.1515) -> (28.6134, 11.2121)
  line L599 (28.6134, 11.2121) -> (28.4386, 11.3012)
  line L600 (28.4386, 11.3012) -> (28.2799, 11.4165)
  line L601 (28.2799, 11.4165) -> (28.1412, 11.5551)
  line L602 (28.1412, 11.5551) -> (28.0259, 11.7138)
  line L603 (28.0259, 11.7138) -> (27.9989, 11.767)
  line L604 (27.9989, 11.767) -> (26.2082, 11.767)
  line L605 (26.2082, 11.767) -> (26.1963, 11.7601)
  line L606 (26.1963, 11.7601) -> (26.045, 11.7196)
  line L607 (26.045, 11.7196) -> (25.8884, 11.7196)
  line L608 (25.8884, 11.7196) -> (25.7371, 11.7601)
  line L609 (25.7371, 11.7601) -> (25.6015, 11.8384)
  line L610 (25.6015, 11.8384) -> (25.5425, 11.8902)
  line L611 (25.5425, 11.8902) -> (21.1657, 16.2669)
  line L612 (21.1657, 16.2669) -> (21.114, 16.3259)
  line L613 (21.114, 16.3259) -> (21.0357, 16.4615)
  line L614 (21.0357, 16.4615) -> (20.9989, 16.5986)
  line L615 (20.9989, 16.5986) -> (20.8462, 16.6482)
  line L616 (20.8462, 16.6482) -> (20.6749, 16.7355)
  line L617 (20.6749, 16.7355) -> (20.5194, 16.8485)
  line L618 (20.5194, 16.8485) -> (20.3835, 16.9844)
  line L619 (20.3835, 16.9844) -> (20.2705, 17.1399)
  line L620 (20.2705, 17.1399) -> (20.1832, 17.3112)
  line L621 (20.1832, 17.3112) -> (20.1238, 17.494)
  line L622 (20.1238, 17.494) -> (20.0938, 17.6839)
  line L623 (20.0938, 17.6839) -> (20.0938, 17.8761)
  line L624 (20.0938, 17.8761) -> (20.1238, 18.066)
  line L625 (20.1238, 18.066) -> (20.1832, 18.2488)
  line L626 (20.1832, 18.2488) -> (20.2705, 18.4201)
  line L627 (20.2705, 18.4201) -> (20.3835, 18.5756)
  line L628 (20.3835, 18.5756) -> (20.5194, 18.7115)
  line L629 (20.5194, 18.7115) -> (20.6749, 18.8245)
  line L630 (20.6749, 18.8245) -> (20.8462, 18.9118)
  line L631 (20.8462, 18.9118) -> (21.029, 18.9712)
  line L632 (21.029, 18.9712) -> (21.2189, 19.0012)
  line L633 (21.2189, 19.0012) -> (21.315, 19.005)
  line L634 (21.315, 19.005) -> (21.865, 19.005)
  line L635 (21.865, 19.005) -> (21.9611, 19.0012)
  line L636 (21.9611, 19.0012) -> (22.151, 18.9712)
  line L637 (22.151, 18.9712) -> (22.3338, 18.9118)
  line L638 (22.3338, 18.9118) -> (22.5051, 18.8245)
  line L639 (22.5051, 18.8245) -> (22.6606, 18.7115)
  line L640 (22.6606, 18.7115) -> (22.7965, 18.5756)
  line L641 (22.7965, 18.5756) -> (22.9095, 18.4201)
  line L642 (22.9095, 18.4201) -> (22.9968, 18.2488)
  line L643 (22.9968, 18.2488) -> (23.0562, 18.066)
  line L644 (23.0562, 18.066) -> (23.0862, 17.8761)
  line L645 (23.0862, 17.8761) -> (23.0862, 17.6839)
  line L646 (23.0862, 17.6839) -> (23.0562, 17.494)
  line L647 (23.0562, 17.494) -> (22.9968, 17.3112)
  line L648 (22.9968, 17.3112) -> (22.9095, 17.1399)
  line L649 (22.9095, 17.1399) -> (22.7965, 16.9844)
  line L650 (22.7965, 16.9844) -> (22.6606, 16.8485)
  line L651 (22.6606, 16.8485) -> (22.5051, 16.7355)
  line L652 (22.5051, 16.7355) -> (22.4316, 16.6981)
  line L653 (22.4316, 16.6981) -> (26.1627, 12.967)
  line L654 (26.1627, 12.967) -> (27.9989, 12.967)
  line L655 (27.9989, 12.967) -> (28.0259, 13.0201)
  line L656 (28.0259, 13.0201) -> (28.1412, 13.1788)
  line L657 (28.1412, 13.1788) -> (28.2799, 13.3175)
  line L658 (28.2799, 13.3175) -> (28.4386, 13.4328)
  line L659 (28.4386, 13.4328) -> (28.6134, 13.5218)
  line L660 (28.6134, 13.5218) -> (28.7999, 13.5824)
  line L661 (28.7999, 13.5824) -> (28.9937, 13.6131)
  line L662 (28.9937, 13.6131) -> (29.0917, 13.617)
  line L663 (29.0917, 13.617) -> (29.5917, 13.617)
  line L664 (29.5917, 13.617) -> (29.6898, 13.6131)
  line L665 (29.6898, 13.6131) -> (29.7326, 13.6063)
  line L666 (29.7326, 13.6063) -> (34.9239, 18.7977)
  line L667 (34.9239, 18.7977) -> (34.9829, 18.8494)
  line L668 (34.9829, 18.8494) -> (35.1186, 18.9277)
  line L669 (35.1186, 18.9277) -> (35.2699, 18.9683)
  line L670 (35.2699, 18.9683) -> (35.3482, 18.9734)
  line L671 (35.3482, 18.9734) -> (41.6943, 18.9734)
  line L672 (41.6943, 18.9734) -> (41.7173, 19.0078)
  line L673 (41.7173, 19.0078) -> (41.8559, 19.1464)
  line L674 (41.8559, 19.1464) -> (42.0189, 19.2553)
  line L675 (42.0189, 19.2553) -> (42.2, 19.3303)
  line L676 (42.2, 19.3303) -> (42.3923, 19.3686)
  line L677 (42.3923, 19.3686) -> (42.4903, 19.3734)
  line L678 (42.4903, 19.3734) -> (43.6903, 19.3734)
  line L679 (43.6903, 19.3734) -> (43.7883, 19.3686)
  line L680 (104.7483, 19.3686) -> (104.9406, 19.3303)
  line L681 (104.9406, 19.3303) -> (105.1217, 19.2553)
  line L682 (105.1217, 19.2553) -> (105.2847, 19.1464)
  line L683 (105.2847, 19.1464) -> (105.4233, 19.0078)
  line L684 (105.4233, 19.0078) -> (105.5322, 18.8448)
  line L685 (105.5322, 18.8448) -> (105.6072, 18.6637)
  line L686 (105.6072, 18.6637) -> (105.6455, 18.4714)
  line L687 (105.6455, 18.4714) -> (105.6455, 18.2754)
  line L688 (105.6455, 18.2754) -> (105.6072, 18.0831)
  line L689 (105.6072, 18.0831) -> (105.5322, 17.902)
  line L690 (105.5322, 17.902) -> (105.4233, 17.739)
  line L691 (105.4233, 17.739) -> (105.2847, 17.6004)
  line L692 (105.2847, 17.6004) -> (105.1217, 17.4915)
  line L693 (105.1217, 17.4915) -> (104.9406, 17.4165)
  line L694 (104.9406, 17.4165) -> (104.7483, 17.3782)
  line L695 (104.7483, 17.3782) -> (104.6503, 17.3734)
  line L696 (104.6503, 17.3734) -> (103.4503, 17.3734)
  line L697 (103.4503, 17.3734) -> (103.3523, 17.3782)
  line L698 (103.3523, 17.3782) -> (103.16, 17.4165)
  line L699 (103.16, 17.4165) -> (102.9789, 17.4915)
  line L700 (102.9789, 17.4915) -> (102.8159, 17.6004)
  line L701 (102.8159, 17.6004) -> (102.6773, 17.739)
  line L702 (102.6773, 17.739) -> (102.6543, 17.7734)
  line L703 (102.6543, 17.7734) -> (96.5567, 17.7734)
  line L704 (96.5567, 17.7734) -> (91.6803, 12.897)
  line L705 (91.6803, 12.897) -> (91.7066, 12.8453)
  line L706 (91.7066, 12.8453) -> (91.7672, 12.6588)
  line L707 (91.7672, 12.6588) -> (91.7979, 12.465)
  line L708 (91.7979, 12.465) -> (91.7979, 12.2689)
  line L709 (91.7979, 12.2689) -> (91.7672, 12.0752)
  line L710 (91.7672, 12.0752) -> (91.7066, 11.8886)
  line L711 (91.7066, 11.8886) -> (91.6175, 11.7138)
  line L712 (91.6175, 11.7138) -> (91.5022, 11.5551)
  line L713 (91.5022, 11.5551) -> (91.3635, 11.4165)
  line L714 (91.3635, 11.4165) -> (91.2049, 11.3012)
  line L715 (91.2049, 11.3012) -> (91.0301, 11.2121)
  line L716 (91.0301, 11.2121) -> (90.8435, 11.1515)
  line L717 (90.8435, 11.1515) -> (90.6498, 11.1208)
  line L718 (90.6498, 11.1208) -> (90.5517, 11.117)
  line L719 (90.5517, 11.117) -> (90.0517, 11.117)
  line L720 (90.0517, 11.117) -> (89.9537, 11.1208)
  line L721 (89.9537, 11.1208) -> (89.7599, 11.1515)
  line L722 (89.7599, 11.1515) -> (89.5734, 11.2121)
  line L723 (89.5734, 11.2121) -> (89.3986, 11.3012)
  line L724 (89.3986, 11.3012) -> (89.2399, 11.4165)
  line L725 (89.2399, 11.4165) -> (89.1012, 11.5551)
  line L726 (89.1012, 11.5551) -> (88.9859, 11.7138)
  line L727 (88.9859, 11.7138) -> (88.9589, 11.767)
  line L728 (88.9589, 11.767) -> (87.1682, 11.767)
  line L729 (87.1682, 11.767) -> (87.1563, 11.7601)
  line L730 (87.1563, 11.7601) -> (87.005, 11.7196)
  line L731 (87.005, 11.7196) -> (86.8484, 11.7196)
  line L732 (86.8484, 11.7196) -> (86.6971, 11.7601)
  line L733 (86.6971, 11.7601) -> (86.5615, 11.8384)
  line L734 (86.5615, 11.8384) -> (86.5025, 11.8902)
  line L735 (86.5025, 11.8902) -> (82.1257, 16.2669)
  line L736 (82.1257, 16.2669) -> (82.074, 16.3259)
  line L737 (82.074, 16.3259) -> (81.9957, 16.4615)
  line L738 (81.9957, 16.4615) -> (81.9589, 16.5986)
  line L739 (81.9589, 16.5986) -> (81.8062, 16.6482)
  line L740 (81.8062, 16.6482) -> (81.6349, 16.7355)
  line L741 (81.6349, 16.7355) -> (81.4794, 16.8485)
  line L742 (81.4794, 16.8485) -> (81.3435, 16.9844)
  line L743 (81.3435, 16.9844) -> (81.2305, 17.1399)
  line L744 (81.2305, 17.1399) -> (81.1432, 17.3112)
  line L745 (81.1432, 17.3112) -> (81.0838, 17.494)
  line L746 (81.0838, 17.494) -> (81.0538, 17.6839)
  line L747 (81.0538, 17.6839) -> (81.0538, 17.8761)
  line L748 (81.0538, 17.8761) -> (81.0838, 18.066)
  line L749 (81.0838, 18.066) -> (81.1432, 18.2488)
  line L750 (81.1432, 18.2488) -> (81.2305, 18.4201)
  line L751 (81.2305, 18.4201) -> (81.3435, 18.5756)
  line L752 (81.3435, 18.5756) -> (81.4794, 18.7115)
  line L753 (81.4794, 18.7115) -> (81.6349, 18.8245)
  line L754 (81.6349, 18.8245) -> (81.8062, 18.9118)
  line L755 (81.8062, 18.9118) -> (81.989, 18.9712)
  line L756 (81.989, 18.9712) -> (82.1789, 19.0012)
  line L757 (82.1789, 19.0012) -> (82.275, 19.005)
  line L758 (82.275, 19.005) -> (82.825, 19.005)
  line L759 (82.825, 19.005) -> (82.9211, 19.0012)
  line L760 (82.9211, 19.0012) -> (83.111, 18.9712)
  line L761 (83.111, 18.9712) -> (83.2938, 18.9118)
  line L762 (83.2938, 18.9118) -> (83.4651, 18.8245)
  line L763 (83.4651, 18.8245) -> (83.6206, 18.7115)
  line L764 (83.6206, 18.7115) -> (83.7565, 18.5756)
  line L765 (83.7565, 18.5756) -> (83.8695, 18.4201)
  line L766 (83.8695, 18.4201) -> (83.9568, 18.2488)
  line L767 (83.9568, 18.2488) -> (84.0162, 18.066)
  line L768 (84.0162, 18.066) -> (84.0462, 17.8761)
  line L769 (84.0462, 17.8761) -> (84.0462, 17.6839)
  line L770 (84.0462, 17.6839) -> (84.0162, 17.494)
  line L771 (84.0162, 17.494) -> (83.9568, 17.3112)
  line L772 (83.9568, 17.3112) -> (83.8695, 17.1399)
  line L773 (83.8695, 17.1399) -> (83.7565, 16.9844)
  line L774 (83.7565, 16.9844) -> (83.6206, 16.8485)
  line L775 (83.6206, 16.8485) -> (83.4651, 16.7355)
  line L776 (83.4651, 16.7355) -> (83.3916, 16.6981)
  line L777 (83.3916, 16.6981) -> (87.1227, 12.967)
  line L778 (87.1227, 12.967) -> (88.9589, 12.967)
  line L779 (88.9589, 12.967) -> (88.9859, 13.0201)
  line L780 (88.9859, 13.0201) -> (89.1012, 13.1788)
  line L781 (89.1012, 13.1788) -> (89.2399, 13.3175)
  line L782 (89.2399, 13.3175) -> (89.3986, 13.4328)
  line L783 (89.3986, 13.4328) -> (89.5734, 13.5218)
  line L784 (89.5734, 13.5218) -> (89.7599, 13.5824)
  line L785 (89.7599, 13.5824) -> (89.9537, 13.6131)
  line L786 (89.9537, 13.6131) -> (90.0517, 13.617)
  line L787 (90.0517, 13.617) -> (90.5517, 13.617)
  line L788 (90.5517, 13.617) -> (90.6498, 13.6131)
  line L789 (90.6498, 13.6131) -> (90.6926, 13.6063)
  line L790 (90.6926, 13.6063) -> (95.8839, 18.7977)
  line L791 (95.8839, 18.7977) -> (95.9429, 18.8494)
  line L792 (95.9429, 18.8494) -> (96.0786, 18.9277)
  line L793 (96.0786, 18.9277) -> (96.2299, 18.9683)
  line L794 (96.2299, 18.9683) -> (96.3082, 18.9734)
  line L795 (96.3082, 18.9734) -> (102.6543, 18.9734)
  line L796 (102.6543, 18.9734) -> (102.6773, 19.0078)
  line L797 (102.6773, 19.0078) -> (102.8159, 19.1464)
  line L798 (102.8159, 19.1464) -> (102.9789, 19.2553)
  line L799 (102.9789, 19.2553) -> (103.16, 19.3303)
  line L800 (103.16, 19.3303) -> (103.3523, 19.3686)
  line L801 (103.3523, 19.3686) -> (103.4503, 19.3734)
  line L802 (103.4503, 19.3734) -> (104.6503, 19.3734)
  line L803 (104.6503, 19.3734) -> (104.7483, 19.3686)
  line L804 (51.3932, 27.5187) -> (51.5445, 27.4782)
  line L805 (51.5445, 27.4782) -> (51.6802, 27.3998)
  line L806 (51.6802, 27.3998) -> (51.7392, 27.3481)
  line L807 (51.7392, 27.3481) -> (56.9296, 22.1576)
  line L808 (56.9296, 22.1576) -> (57.3233, 22.1576)
  line L809 (57.3233, 22.1576) -> (57.3233, 22.7826)
  line L810 (57.3233, 22.7826) -> (60.3233, 22.7826)
  line L811 (60.3233, 22.7826) -> (60.3233, 20.3326)
  line L812 (60.3233, 20.3326) -> (57.3233, 20.3326)
  line L813 (57.3233, 20.3326) -> (57.3233, 20.9576)
  line L814 (57.3233, 20.9576) -> (56.6811, 20.9576)
  line L815 (56.6811, 20.9576) -> (56.6028, 20.9628)
  line L816 (56.6028, 20.9628) -> (56.4515, 21.0033)
  line L817 (56.4515, 21.0033) -> (56.3158, 21.0816)
  line L818 (56.3158, 21.0816) -> (56.2568, 21.1334)
  line L819 (56.2568, 21.1334) -> (51.0664, 26.3238)
  line L820 (51.0664, 26.3238) -> (47.6346, 26.3238)
  line L821 (47.6346, 26.3238) -> (47.065, 25.7542)
  line L822 (47.065, 25.7542) -> (47.006, 25.7025)
  line L823 (47.006, 25.7025) -> (46.8703, 25.6241)
  line L824 (46.8703, 25.6241) -> (46.719, 25.5836)
  line L825 (46.719, 25.5836) -> (46.6407, 25.5785)
  line L826 (46.6407, 25.5785) -> (44.5445, 25.5785)
  line L827 (44.5445, 25.5785) -> (44.5215, 25.5441)
  line L828 (44.5215, 25.5441) -> (44.3829, 25.4055)
  line L829 (44.3829, 25.4055) -> (44.2199, 25.2966)
  line L830 (44.2199, 25.2966) -> (44.0388, 25.2215)
  line L831 (44.0388, 25.2215) -> (43.8465, 25.1833)
  line L832 (43.8465, 25.1833) -> (43.7485, 25.1785)
  line L833 (43.7485, 25.1785) -> (42.5485, 25.1785)
  line L834 (42.5485, 25.1785) -> (42.4505, 25.1833)
  line L835 (42.4505, 25.1833) -> (42.2582, 25.2215)
  line L836 (42.2582, 25.2215) -> (42.0771, 25.2966)
  line L837 (42.0771, 25.2966) -> (41.9141, 25.4055)
  line L838 (41.9141, 25.4055) -> (41.7755, 25.5441)
  line L839 (41.7755, 25.5441) -> (41.7525, 25.5785)
  line L840 (41.7525, 25.5785) -> (27.737, 25.5785)
  line L841 (27.737, 25.5785) -> (23.09, 20.9315)
  line L842 (23.09, 20.9315) -> (23.09, 19.4378)
  line L843 (23.09, 19.4378) -> (23.0741, 19.3286)
  line L844 (23.0741, 19.3286) -> (23.0187, 19.2154)
  line L845 (23.0187, 19.2154) -> (22.9296, 19.1263)
  line L846 (22.9296, 19.1263) -> (22.8164, 19.0709)
  line L847 (22.8164, 19.0709) -> (22.7072, 19.055)
  line L848 (22.7072, 19.055) -> (20.4728, 19.055)
  line L849 (20.4728, 19.055) -> (20.3636, 19.0709)
  line L850 (20.3636, 19.0709) -> (20.2504, 19.1263)
  line L851 (20.2504, 19.1263) -> (20.1613, 19.2154)
  line L852 (20.1613, 19.2154) -> (20.1059, 19.3286)
  line L853 (20.1059, 19.3286) -> (20.09, 19.4378)
  line L854 (20.09, 19.4378) -> (20.09, 21.1222)
  line L855 (20.09, 21.1222) -> (20.1059, 21.2314)
  line L856 (20.1059, 21.2314) -> (20.1613, 21.3446)
  line L857 (20.1613, 21.3446) -> (20.2504, 21.4337)
  line L858 (20.2504, 21.4337) -> (20.3636, 21.4891)
  line L859 (20.3636, 21.4891) -> (20.4728, 21.505)
  line L860 (20.4728, 21.505) -> (21.9665, 21.505)
  line L861 (21.9665, 21.505) -> (27.0642, 26.6027)
  line L862 (27.0642, 26.6027) -> (27.1232, 26.6545)
  line L863 (27.1232, 26.6545) -> (27.2589, 26.7328)
  line L864 (27.2589, 26.7328) -> (27.4102, 26.7733)
  line L865 (27.4102, 26.7733) -> (27.4885, 26.7785)
  line L866 (27.4885, 26.7785) -> (41.7525, 26.7785)
  line L867 (41.7525, 26.7785) -> (41.7755, 26.8129)
  line L868 (41.7755, 26.8129) -> (41.9141, 26.9515)
  line L869 (41.9141, 26.9515) -> (42.0771, 27.0604)
  line L870 (42.0771, 27.0604) -> (42.2582, 27.1354)
  line L871 (42.2582, 27.1354) -> (42.4505, 27.1737)
  line L872 (42.4505, 27.1737) -> (42.5485, 27.1785)
  line L873 (42.5485, 27.1785) -> (43.7485, 27.1785)
  line L874 (43.7485, 27.1785) -> (43.8465, 27.1737)
  line L875 (43.8465, 27.1737) -> (44.0388, 27.1354)
  line L876 (44.0388, 27.1354) -> (44.2199, 27.0604)
  line L877 (44.2199, 27.0604) -> (44.3829, 26.9515)
  line L878 (44.3829, 26.9515) -> (44.5215, 26.8129)
  line L879 (44.5215, 26.8129) -> (44.5445, 26.7785)
  line L880 (44.5445, 26.7785) -> (46.3922, 26.7785)
  line L881 (46.3922, 26.7785) -> (46.9618, 27.3481)
  line L882 (46.9618, 27.3481) -> (47.0208, 27.3998)
  line L883 (47.0208, 27.3998) -> (47.1565, 27.4782)
  line L884 (47.1565, 27.4782) -> (47.3078, 27.5187)
  line L885 (47.3078, 27.5187) -> (47.3861, 27.5238)
  line L886 (47.3861, 27.5238) -> (51.3149, 27.5238)
  line L887 (51.3149, 27.5238) -> (51.3932, 27.5187)
  line L888 (112.3532, 27.5187) -> (112.5045, 27.4782)
  line L889 (112.5045, 27.4782) -> (112.6402, 27.3998)
  line L890 (112.6402, 27.3998) -> (112.6992, 27.3481)
  line L891 (112.6992, 27.3481) -> (117.8896, 22.1576)
  line L892 (117.8896, 22.1576) -> (118.2833, 22.1576)
  line L893 (118.2833, 22.1576) -> (118.2833, 22.7826)
  line L894 (118.2833, 22.7826) -> (121.2833, 22.7826)
  line L895 (121.2833, 22.7826) -> (121.2833, 20.3326)
  line L896 (121.2833, 20.3326) -> (118.2833, 20.3326)
  line L897 (118.2833, 20.3326) -> (118.2833, 20.9576)
  line L898 (118.2833, 20.9576) -> (117.6411, 20.9576)
  line L899 (117.6411, 20.9576) -> (117.5628, 20.9628)
  line L900 (117.5628, 20.9628) -> (117.4115, 21.0033)
  line L901 (117.4115, 21.0033) -> (117.2758, 21.0816)
  line L902 (117.2758, 21.0816) -> (117.2168, 21.1334)
  line L903 (117.2168, 21.1334) -> (112.0264, 26.3238)
  line L904 (112.0264, 26.3238) -> (108.5946, 26.3238)
  line L905 (108.5946, 26.3238) -> (108.025, 25.7542)
  line L906 (108.025, 25.7542) -> (107.966, 25.7025)
  line L907 (107.966, 25.7025) -> (107.8303, 25.6241)
  line L908 (107.8303, 25.6241) -> (107.679, 25.5836)
  line L909 (107.679, 25.5836) -> (107.6007, 25.5785)
  line L910 (107.6007, 25.5785) -> (105.5045, 25.5785)
  line L911 (105.5045, 25.5785) -> (105.4815, 25.5441)
  line L912 (105.4815, 25.5441) -> (105.3429, 25.4055)
  line L913 (105.3429, 25.4055) -> (105.1799, 25.2966)
  line L914 (105.1799, 25.2966) -> (104.9988, 25.2215)
  line L915 (104.9988, 25.2215) -> (104.8065, 25.1833)
  line L916 (104.8065, 25.1833) -> (104.7085, 25.1785)
  line L917 (104.7085, 25.1785) -> (103.5085, 25.1785)
  line L918 (103.5085, 25.1785) -> (103.4105, 25.1833)
  line L919 (103.4105, 25.1833) -> (103.2182, 25.2215)
  line L920 (103.2182, 25.2215) -> (103.0371, 25.2966)
  line L921 (103.0371, 25.2966) -> (102.8741, 25.4055)
  line L922 (102.8741, 25.4055) -> (102.7355, 25.5441)
  line L923 (102.7355, 25.5441) -> (102.7125, 25.5785)
  line L924 (102.7125, 25.5785) -> (88.697, 25.5785)
  line L925 (88.697, 25.5785) -> (84.05, 20.9315)
  line L926 (84.05, 20.9315) -> (84.05, 19.4378)
  line L927 (84.05, 19.4378) -> (84.0341, 19.3286)
  line L928 (84.0341, 19.3286) -> (83.9787, 19.2154)
  line L929 (83.9787, 19.2154) -> (83.8896, 19.1263)
  line L930 (83.8896, 19.1263) -> (83.7764, 19.0709)
  line L931 (83.7764, 19.0709) -> (83.6672, 19.055)
  line L932 (83.6672, 19.055) -> (81.4328, 19.055)
  line L933 (81.4328, 19.055) -> (81.3236, 19.0709)
  line L934 (81.3236, 19.0709) -> (81.2104, 19.1263)
  line L935 (81.2104, 19.1263) -> (81.1213, 19.2154)
  line L936 (81.1213, 19.2154) -> (81.0659, 19.3286)
  line L937 (81.0659, 19.3286) -> (81.05, 19.4378)
  line L938 (81.05, 19.4378) -> (81.05, 21.1222)
  line L939 (81.05, 21.1222) -> (81.0659, 21.2314)
  line L940 (81.0659, 21.2314) -> (81.1213, 21.3446)
  line L941 (81.1213, 21.3446) -> (81.2104, 21.4337)
  line L942 (81.2104, 21.4337) -> (81.3236, 21.4891)